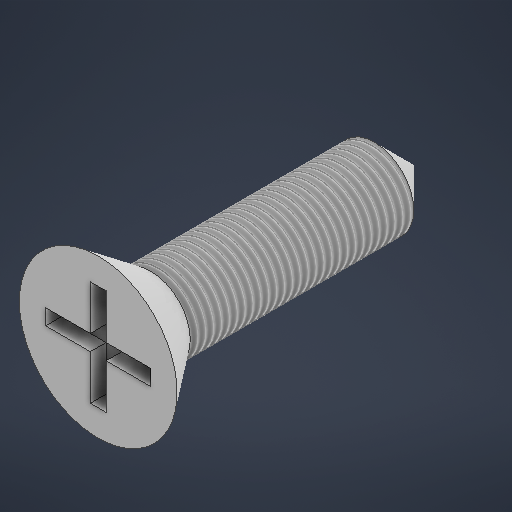
# Autodesk Inventor part: screw
Saved by Autodesk Inventor 2025.2 (Build 292293000, 293)
## iProperties
Created: 2025-01-18
Part Number: screw
Material: Generic
Document SubType Name: Modeling
Designer: user
Density: 1 g/cm^3
Appearance: Default
Author: user
Autodesk Inventor part; units mm, degrees
ref_plane "YZ Plane" through (0, 0, 0) normal (1, 0, 0) x (0, 1, 0)
ref_plane "XZ Plane" through (0, 0, 0) normal (0, 1, 0) x (-1, 0, 0)
sketch "Sketch1" plane through (0, 0, 0) normal (0, 0, 1) x (1, 0, 0)
  circle A0 centre (0, 0) radius 7.5
  dimension "d0" = 15
  constraints: 1 centre point, 1 coincident
  measures "d0" diameter of A0
extrude "Extrusion1" add sketch "Sketch1" along normal blind 50
ref_plane "Work Plane1" through (0, 0, 60) normal (0, 0, 1) x (1, 0, 0)
sketch "Sketch2" plane through (0, 0, 60) normal (0, 0, 1) x (1, 0, 0)
  circle A0 centre (0, 0) radius 15
  dimension "d4" = 30
  constraints: 1 centre point, 1 coincident
  measures "d4" diameter of A0
loft "Loft1" add profiles "Sketch2" section 1 edges at (-7.5, 0, 50)
chamfer "Chamfer1" distance 7.5 angle 45 1 edges at (-7.5, 0, 0)
thread "Thread1" size "M15x1.5" class "6g" standard "ANSI Metric M Profile" length 70
sketch "Sketch3" plane through (0, 0, 60) normal (0, 0, 1) x (1, 0, 0)
  line L0 (10, -1.5) -> (-10, -1.5)
  line L1 (-10, -1.5) -> (-10, 1.5)
  line L2 (-10, 1.5) -> (10, 1.5)
  line L3 (10, 1.5) -> (10, -1.5)
  line L4 (10, -1.5) -> (-10, 1.5) construction
  line L5 (-10, -1.5) -> (10, 1.5) construction
  line L6 (1.5, -10) -> (-1.5, -10)
  line L7 (-1.5, -10) -> (-1.5, 10)
  line L8 (-1.5, 10) -> (1.5, 10)
  line L9 (1.5, 10) -> (1.5, -10)
  line L10 (1.5, -10) -> (-1.5, 10) construction
  line L11 (-1.5, -10) -> (1.5, 10) construction
  point P0 (0, 0)
  point P1 (-1.5, 1.5)
  point P2 (-1.5, -1.5)
  point P3 (1.5, -1.5)
  point P4 (1.5, 1.5)
  dimension "d14" = 20
  dimension "d15" = 3
  dimension "d16" = 3
  dimension "d17" = 20
  constraints: 24 end point, 4 midpoint, 4 parallel, 2 horizontal, 2 perpendicular
  measures "d14" distance of L1.end L2.end
  measures "d15" distance of L0.end L1.end
  measures "d16" distance of L7.end L8.end
  measures "d17" distance of L6.end L7.end
extrude "Extrusion2" cut sketch "Sketch3" against normal blind 3
body "Solid1"
